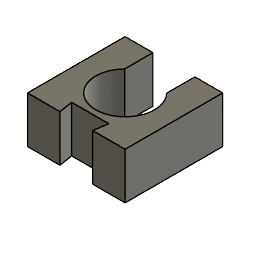
E_suporte_sensor_pressao (Autodesk Fusion 360 design; units mm, degrees)
Autodesk Fusion 360 part; units mm, degrees
sketch "Esboço1" plane through (0, 0, 0) normal (0, 1, 0) x (1, 0, 0)
  line L0 (8, -8) -> (-8, -8)
  line L1 (-8, -8) -> (-8, 8)
  line L2 (8, 8) -> (8, -8)
  line L3 (8, -8) -> (-8, 8) construction
  line L4 (-8, -8) -> (8, 8) construction
  line L5 (4, 4.8023) -> (4, 8)
  arc A0 (-4, 4.8023) -> (4, 4.8023) centre (0, 0) ccw
  line L6 (-4, 4.8023) -> (-4, 8)
  line L7 (-8, 8) -> (-4, 8)
  line L8 (4, 8) -> (8, 8)
  dimension "d1" = 12.5
  dimension "d2" = 16
  dimension "d3" = 16
  constraint coincident A0.centre origin
  constraint horizontal L0
  constraint perpendicular L0 L1
  constraint parallel L1 L2
  constraint coincident L3 A0.centre
  constraint coincident L4 A0.centre
  constraint vertical L5
  constraint perpendicular L2 L8
  constraint perpendicular L6 L7
  constraint perpendicular L1 L7
  measures "d1" diameter of A0
  measures "d2" distance of L1.end L2.start
  measures "d3" distance of L0.end L1.end
sketch "Esboço2" plane through (0, 0, 0) normal (0, 1, 0) x (1, 0, 0)
ref_plane "Plano de trabalho3" through (0, 0, 0) normal (0, 1, 0) x (0, 0, 1)
sketch "Esboço3" plane through (0, 0, 0) normal (0, 1, 0) x (1, 0, 0)
  line L0 (-10.5, 10.5) -> (-10.5, -10.5)
  line L1 (-10.5, -10.5) -> (10.5, -10.5)
  line L2 (10.5, -10.5) -> (10.5, 10.5)
  line L3 (10.5, 10.5) -> (-10.5, -10.5) construction
  line L4 (-10.5, 10.5) -> (10.5, -10.5) construction
  line L5 (0, 10.5) -> (0, 6)
  line L6 (0, 10.5) -> (0, 6)
  arc A0 (-4.5, 4.4091) -> (4.5, 4.4091) centre (0, 0) ccw
  line L7 (10.5, 10.5) -> (4.5, 10.5)
  line L8 (-4.5, 10.5) -> (-10.5, 10.5)
  line L9 (-10.5, 10.5) -> (-4.5, 10.5)
  line L10 (-4.5, 10.5) -> (-4.5, 4.4091)
  line L11 (10.5, 10.5) -> (4.5, 10.5)
  line L12 (4.5, 10.5) -> (4.5, 4.4091)
  dimension "d11" = 21
  dimension "d12" = 21
  dimension "d13" = 12.6
  dimension "d31" = 6
  dimension "d32" = 6
  constraint horizontal L7
  constraint perpendicular L0 L7
  constraint parallel L1 L7
  constraint parallel L0 L2
  constraint coincident L3 A0.centre
  constraint coincident L4 A0.centre
  constraint coincident A0.centre origin
  constraint vertical L5
  constraint vertical L6
  constraint collinear L7 L8
  constraint perpendicular L9 L10
  constraint perpendicular L2 L11
  constraint perpendicular L7 L12
  measures "d11" distance of L0.end L1.end
  measures "d12" distance of L0.start L0.end
  measures "d13" diameter of A0
  measures "d31" distance of L0.start L8.start
  measures "d32" distance of L2.end L7.end
extrude "Extrusão2" add sketch "Esboço3" along normal blind 10 makes body 1
sketch "Esboço5" plane through (0, 10, 0) normal (0, 1, 0) x (-1, 0, 0)
  line L0 (4.5, -10.5) -> (10.5, -10.5)
  line L1 (10.5, -10.5) -> (10.5, 10.5)
  line L2 (10.5, 10.5) -> (-10.5, 10.5)
  line L3 (-10.5, 10.5) -> (-10.5, -10.5)
  line L4 (-10.5, -10.5) -> (-4.5, -10.5)
  arc A0 (4.5, -4.4091) -> (-4.5, -4.4091) centre (0, 0) ccw
  line L5 (0, 10.5) -> (3.5, 10.5)
  line L6 (0, 10.5) -> (-3.5, 10.5)
  line L7 (0, 10.5) -> (4, 10.5)
  line L8 (4, 10.5) -> (4, 7.5)
  line L9 (4, 7.5) -> (0, 7.5)
  line L10 (0, 10.5) -> (-4, 10.5)
  line L11 (-4, 10.5) -> (-4, 7.5)
  line L12 (-4, 7.5) -> (0, 7.5)
  line L13 (0, 7.5) -> (0, 10.5)
  line L14 (4, 7.5) -> (3.5, 10.5)
  line L15 (-3.5, 10.5) -> (-4, 7.5)
  line L16 (-4.5, -10.5) -> (-4.5, -4.4091)
  line L17 (4.5, -4.4091) -> (4.5, -10.5)
  dimension "d23" = 3.5
  dimension "d24" = 3.5
  dimension "d27" = 4
  dimension "d28" = 3
  dimension "d29" = 4
  dimension "d30" = 3
  constraint midpoint L2 L5.start
  constraint parallel L2 L5
  constraint parallel L2 L6
  constraint horizontal L7
  constraint vertical L8
  constraint horizontal L9
  constraint horizontal L10
  constraint vertical L11
  constraint horizontal L12
  constraint vertical L13
  measures "d23" distance of L5.start L5.end
  measures "d24" distance of L5.start L6.end
  measures "d27" distance of L5.start L7.end
  measures "d28" distance of L5.start L9.end
  measures "d29" distance of L5.start L10.end
  measures "d30" distance of L5.start L9.end
extrude "Extrusão3" cut sketch "Esboço5" against normal blind 25 contours L2 L5 L7 L9 L13 L14 | L2 L6 L10 L12 L13 L15 bodies 1
copy_body "Corpo -> Componente2" bodies 1 removing the originals makes body 2 in component "Clip de Fixação"
component "Clip de Fixação" placed x (1, 0, 0) y (0, 1, 0) z (0, 0, 1) at (0, 0, 0)
